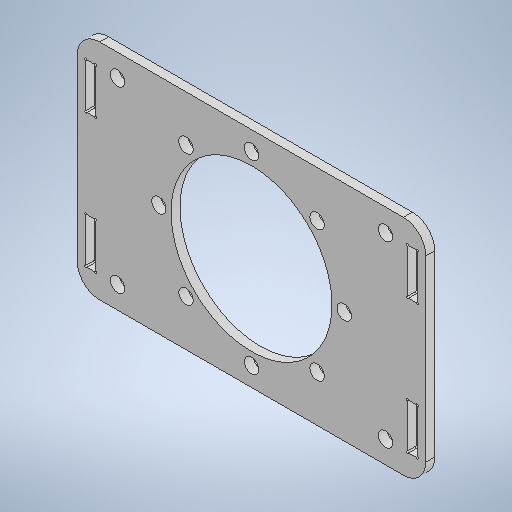
# Autodesk Inventor part: plate_oo
Saved by Autodesk Inventor 2025.3 (Build 293356000, 356)
## iProperties
Created: 2026-10-04
Part Number: plate_oo
Material: 一般
Document SubType Name: Modeling
Designer: yunto
Density: 1 g/cm^3
Appearance: 既定
Author: yunto
Autodesk Inventor part; units mm, degrees
ref_plane "YZ Plane" through (0, 0, 0) normal (1, 0, 0) x (0, 1, 0)
ref_plane "XZ Plane" through (0, 0, 0) normal (0, 1, 0) x (-1, 0, 0)
ref_plane "XY Plane" through (0, 0, 0) normal (0, 0, 1) x (1, 0, 0)
sketch "スケッチ1" plane through (0, 0, 0) normal (0, 0, 1) x (1, 0, 0)
  line L0 (39, -25) -> (-39, -25)
  line L1 (-39, -25) -> (-39, 25)
  line L2 (-39, 25) -> (39, 25) construction
  line L3 (39, 25) -> (39, -25)
  line L4 (39, -25) -> (-39, 25) construction
  line L5 (-39, -25) -> (39, 25) construction
  line L6 (-30, 20) -> (-30, -20) construction
  circle A0 centre (-30, 20) radius 1.6
  circle A1 centre (-30, -20) radius 1.6
  line L7 (-30, 0) -> (0, 0) construction
  line L8 (0, 25) -> (0, -25) construction
  circle A2 centre (30, 20) radius 1.6
  circle A3 centre (30, -20) radius 1.6
  line L9 (-37.1, -9.9) -> (-34.9, -9.9)
  line L10 (-34.9, -9.9) -> (-34.9, -20.1)
  line L11 (-34.9, -20.1) -> (-37.1, -20.1)
  line L12 (-37.1, -20.1) -> (-37.1, -9.9)
  circle A4 centre (-37.1, -9.9) radius 0.25
  circle A5 centre (-34.9, -9.9) radius 0.25
  circle A6 centre (-37.1, -20.1) radius 0.25
  circle A7 centre (-34.9, -20.1) radius 0.25
  line L13 (-36, -9.9) -> (-36, -20.1) construction
  line L14 (-37.1, 9.9) -> (-34.9, 9.9)
  line L15 (-34.9, 9.9) -> (-34.9, 20.1)
  line L16 (-34.9, 20.1) -> (-37.1, 20.1)
  line L17 (-37.1, 20.1) -> (-37.1, 9.9)
  circle A8 centre (-37.1, 9.9) radius 0.25
  circle A9 centre (-34.9, 9.9) radius 0.25
  circle A10 centre (-37.1, 20.1) radius 0.25
  circle A11 centre (-34.9, 20.1) radius 0.25
  line L18 (37.1, -9.9) -> (34.9, -9.9)
  line L19 (34.9, -9.9) -> (34.9, -20.1)
  line L20 (34.9, -20.1) -> (37.1, -20.1)
  line L21 (37.1, -20.1) -> (37.1, -9.9)
  circle A12 centre (37.1, -9.9) radius 0.25
  circle A13 centre (34.9, -9.9) radius 0.25
  circle A14 centre (37.1, -20.1) radius 0.25
  circle A15 centre (34.9, -20.1) radius 0.25
  line L22 (37.1, 20.1) -> (37.1, 9.9)
  line L23 (37.1, 9.9) -> (34.9, 9.9)
  line L24 (34.9, 9.9) -> (34.9, 20.1)
  line L25 (34.9, 20.1) -> (37.1, 20.1)
  circle A16 centre (37.1, 20.1) radius 0.25
  circle A17 centre (34.9, 20.1) radius 0.25
  circle A18 centre (34.9, 9.9) radius 0.25
  circle A19 centre (37.1, 9.9) radius 0.25
  line L26 (-22.9, -9.9) -> (-25.1, -9.9)
  line L27 (-25.1, -9.9) -> (-25.1, -20.1)
  line L28 (-25.1, -20.1) -> (-22.9, -20.1)
  line L29 (-22.9, -20.1) -> (-22.9, -9.9)
  circle A20 centre (-22.9, -9.9) radius 0.25
  circle A21 centre (-25.1, -9.9) radius 0.25
  circle A22 centre (-22.9, -20.1) radius 0.25
  circle A23 centre (-25.1, -20.1) radius 0.25
  circle A24 centre (-22.9, 9.9) radius 0.25
  line L30 (-22.9, 9.9) -> (-25.1, 9.9)
  circle A25 centre (-25.1, 9.9) radius 0.25
  line L31 (-25.1, 9.9) -> (-25.1, 20.1)
  line L32 (-22.9, 20.1) -> (-22.9, 9.9)
  circle A26 centre (-22.9, 20.1) radius 0.25
  circle A27 centre (-25.1, 20.1) radius 0.25
  line L33 (-25.1, 20.1) -> (-22.9, 20.1)
  circle A28 centre (22.9, -9.9) radius 0.25
  line L34 (22.9, -9.9) -> (25.1, -9.9)
  circle A29 centre (25.1, -9.9) radius 0.25
  line L35 (25.1, -9.9) -> (25.1, -20.1)
  line L36 (22.9, -20.1) -> (22.9, -9.9)
  circle A30 centre (22.9, -20.1) radius 0.25
  circle A31 centre (25.1, -20.1) radius 0.25
  line L37 (25.1, -20.1) -> (22.9, -20.1)
  circle A32 centre (25.1, 20.1) radius 0.25
  line L38 (22.9, 20.1) -> (22.9, 9.9)
  line L39 (22.9, 9.9) -> (25.1, 9.9)
  line L40 (25.1, 9.9) -> (25.1, 20.1)
  circle A33 centre (22.9, 20.1) radius 0.25
  circle A34 centre (22.9, 9.9) radius 0.25
  circle A35 centre (25.1, 9.9) radius 0.25
  line L41 (25.1, 20.1) -> (22.9, 20.1)
  circle A36 centre (0, 0) radius 18
  circle A37 centre (0, 20.75) radius 1.6
  line L42 (0, 0) -> (0, 20.75) construction
  circle A38 centre (-14.6725, 14.6725) radius 1.6
  circle A39 centre (-20.75, 0) radius 1.6
  circle A40 centre (-14.6725, -14.6725) radius 1.6
  circle A41 centre (0, -20.75) radius 1.6
  circle A42 centre (14.6725, -14.6725) radius 1.6
  circle A43 centre (20.75, 0) radius 1.6
  circle A44 centre (14.6725, 14.6725) radius 1.6
  line L43 (-39, 25) -> (39, 25) construction
  line L44 (39, 25) -> (39, 25)
  line L45 (39, 25) -> (-39, 25)
  line L46 (-39, 25) -> (-39, 25)
  point P0 (-36, -15)
  point P1 (-36, -15)
  point P2 (35.15, -20.1)
  point P3 (34.9, -19.85)
  point P4 (34.9, -10.15)
  point P5 (35.15, -9.9)
  point P6 (36.85, -9.9)
  point P7 (37.1, -10.15)
  point P8 (37.1, -19.85)
  point P9 (36.85, -20.1)
  point P10 (37.1, 19.85)
  point P11 (37.1, 10.15)
  point P12 (36.85, 9.9)
  point P13 (35.15, 9.9)
  point P14 (34.9, 10.15)
  point P15 (34.9, 19.85)
  point P16 (35.15, 20.1)
  point P17 (36.85, 20.1)
  point P18 (-36.85, 9.9)
  point P19 (-37.1, 10.15)
  point P20 (-37.1, 19.85)
  point P21 (-36.85, 20.1)
  point P22 (-35.15, 20.1)
  point P23 (-34.9, 19.85)
  point P24 (-34.9, 10.15)
  point P25 (-35.15, 9.9)
  point P26 (-35.15, -20.1)
  point P27 (-36.85, -20.1)
  point P28 (-37.1, -19.85)
  point P29 (-37.1, -10.15)
  point P30 (-36.85, -9.9)
  point P31 (-35.15, -9.9)
  point P32 (-34.9, -10.15)
  point P33 (-34.9, -19.85)
  point P34 (25.1, -10.15)
  point P35 (25.1, -19.85)
  point P36 (24.85, -20.1)
  point P37 (23.15, -20.1)
  point P38 (22.9, -19.85)
  point P39 (22.9, -10.15)
  point P40 (23.15, -9.9)
  point P41 (24.85, -9.9)
  point P42 (-24.85, 20.1)
  point P43 (-23.15, 20.1)
  point P44 (-22.9, 19.85)
  point P45 (-22.9, 10.15)
  point P46 (-23.15, 9.9)
  point P47 (-24.85, 9.9)
  point P48 (-25.1, 10.15)
  point P49 (-25.1, 19.85)
  point P50 (-23.15, -20.1)
  point P51 (-24.85, -20.1)
  point P52 (-25.1, -19.85)
  point P53 (-25.1, -10.15)
  point P54 (-24.85, -9.9)
  point P55 (-23.15, -9.9)
  point P56 (-22.9, -10.15)
  point P57 (-22.9, -19.85)
  point P58 (22.9, 19.85)
  point P59 (23.15, 20.1)
  point P60 (24.85, 20.1)
  point P61 (25.1, 19.85)
  point P62 (25.1, 10.15)
  point P63 (24.85, 9.9)
  point P64 (23.15, 9.9)
  point P65 (22.9, 10.15)
  dimension "d10" = 3.2
  dimension "d11" = 40
  dimension "d12" = 50
  dimension "d17" = 6
  dimension "d18" = 15
  dimension "d20" = 60
  dimension "d21" = 10.2
  dimension "d22" = 2.2
  dimension "d23" = 0.5
  dimension "d24" = 3
  dimension "d37" = 36
  dimension "d38" = 3.2
  dimension "d41" = 360
  dimension "d43" = 20.75
  dimension "d44" = 25
  dimension "d45" = 0
  constraints: 94 end point, 58 symmetric about line, 45 centre point, 36 coincident, 11 midpoint, 5 parallel, 4 equal radius, 4 horizontal, 3 perpendicular, 2 collinear, 2 vertical, 47 other
  measures "d10" diameter of A0
  measures "d11" distance of L6.start L6.end
  measures "d12" distance of L0.end L1.end
  measures "d17" distance from line of L6 point (-36, -15)
  measures "d18" distance from line of point (-36, -15) L7
  measures "d20" horizontal distance of A2.centre L7.start
  measures "d21" distance of L11.end L9.start
  measures "d22" distance of L10.end L11.end
  measures "d23" diameter of A5
  measures "d24" distance from line of L1 point (-36, -15)
  measures "d37" diameter of A36
  measures "d38" diameter of A37
  measures "d43" distance of L42.start L42.end
  measures "d44" distance from line of L45 L42.start
  measures "d45" distance of point (0, 0) L42.start
extrude "押し出し1" add sketch "スケッチ1" along normal blind 2 contours L0 L1 L45 L3 | A21 L27 L26 | L26 L27 A21 | L26 A20 L29 A22 L28 A23 L27 A21 | A20 L29 L26 | L26 L29 A20 | A23 L28 L27 | L27 L28 A23 | A22 L28 L29 | L29 L28 A22 | A24 L30 L32 | L32 L30 A24 | A24 L30 A25 L31 A27 L33 A26 L32 | A26 L33 L32 | L32 L33 A26 | A25 L31 L30 | L30 L31 A25 | L33 L31 A27 | A27 L31 L33 | L34 L36 A28 | L34 A29 L35 A31 L37 A30 L36 A28 | A28 L36 L34 | A29 L35 L34 | L34 L35 A29 | A30 L37 L36 | L36 L37 A30 | A31 L37 L35 | L35 L37 A31 | A32 L40 L41 | L41 L40 A32 | A32 L40 A35 L39 A34 L38 A33 L41 | L41 L38 A33 | A33 L38 L41 | A35 L39 L40 | L40 L39 A35 | A34 L39 L38 | L38 L39 A34
fillet "フィレット1" radius 5 4 edges at (-39, -25, 1) (39, -25, 1) (-39, 25, 1) (39, 25, 1)
